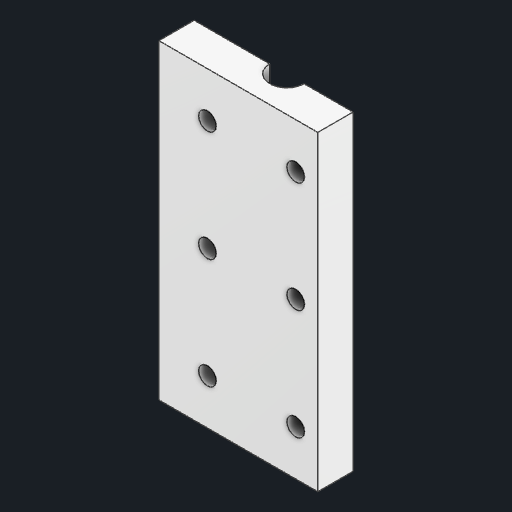
# Autodesk Inventor part: stand L_v3
Saved by Autodesk Inventor 2026.3 (Build 303398000, 398)
## iProperties
Created: 2026-09-14
Part Number: stand L_v3
Material: PBT 플라스틱
Document SubType Name: Modeling
Designer: khw
Density: 1.31 g/cm^3
Appearance: 매끄러움 - 흰색
Author: khw
Autodesk Inventor part; units mm, degrees
ref_plane "YZ Plane" through (0, 0, 0) normal (1, 0, 0) x (0, 1, 0)
ref_plane "XZ Plane" through (0, 0, 0) normal (0, 1, 0) x (-1, 0, 0)
sketch "스케치1" plane through (0, 0, 0) normal (1, 0, 0) x (0, 1, 0)
  circle A0 centre (0, 0) radius 12.5
  line L0 (-15.5, 15.5) -> (15.5, 15.5) construction
  line L1 (15.5, 15.5) -> (15.5, -15.5) construction
  line L2 (15.5, -15.5) -> (-15.5, -15.5) construction
  line L3 (-15.5, -15.5) -> (-15.5, 15.5) construction
  line L4 (-15.5, 15.5) -> (15.5, -15.5) construction
  line L5 (15.5, 15.5) -> (-15.5, -15.5) construction
  circle A1 centre (15.5, 15.5) radius 2
  circle A2 centre (15.5, -15.5) radius 2
  circle A3 centre (-15.5, -15.5) radius 2
  circle A4 centre (-15.5, 15.5) radius 2
  line L6 (0, 59) -> (0, -59) construction
  circle A5 centre (0, 59) radius 4.1
  circle A6 centre (0, -59) radius 4.1
  line L7 (0, 0) -> (-40, 0) construction
  arc A7 (-23.5, 0) -> (-40, 46.5) centre (-97.2727, 0) ccw
  line L8 (-40, 46.5) -> (-40, 79)
  line L9 (-40, 79) -> (30.5, 79)
  line L10 (30.5, 79) -> (30.5, -0.2641)
  circle A8 centre (0, 59) radius 12.5
  line L11 (-22, -22) -> (22, -22)
  line L12 (22, -22) -> (22, 22)
  line L13 (22, 22) -> (-12.9799, 22)
  line L14 (-22, 22) -> (-22, -22)
  line L15 (-22, -22) -> (22, 22) construction
  line L16 (22, -22) -> (-22, 22) construction
  arc A9 (-22.7897, 30.0588) -> (-30, 46.5) centre (-63.5156, 22) ccw
  line L17 (0, 46.5) -> (-30, 46.5)
  line L18 (0, 46.5) -> (5, 46.5)
  line L19 (5, 46.5) -> (12, 46.5)
  line L20 (22, 36.5) -> (22, 22)
  arc A10 (-22.7897, 30.0588) -> (-12.9799, 22) centre (-12.9799, 32) ccw
  line L21 (5, 22) -> (5, 46.5)
  line L22 (-5, 22) -> (-5, 46.5)
  arc A11 (22, 36.5) -> (12, 46.5) centre (12, 36.5) ccw
  line L23 (0, -59) -> (0, 59) construction
  circle A12 centre (0, -59) radius 4.1
  arc A13 (-40, -46.5) -> (-23.5, 0) centre (-97.2727, 0) ccw
  line L24 (-40, -46.5) -> (-40, -79)
  line L25 (-40, -79) -> (30.5, -79)
  line L26 (30.5, -79) -> (30.5, 0.2641)
  circle A14 centre (0, -59) radius 12.5
  line L27 (22, -22) -> (-12.9799, -22)
  arc A15 (-30, -46.5) -> (-22.7897, -30.0588) centre (-63.5156, -22) ccw
  line L28 (0, -46.5) -> (-30, -46.5)
  line L29 (0, -46.5) -> (5, -46.5)
  line L30 (5, -46.5) -> (12, -46.5)
  line L31 (22, -36.5) -> (22, -22)
  arc A16 (-12.9799, -22) -> (-22.7897, -30.0588) centre (-12.9799, -32) ccw
  line L32 (5, -22) -> (5, -46.5)
  line L33 (-5, -22) -> (-5, -46.5)
  arc A17 (12, -46.5) -> (22, -36.5) centre (12, -36.5) ccw
  point P0 (30.5, -0.2641)
  point P1 (-12.9799, -22)
  dimension "d16" = 25
  dimension "d0" = 25
  dimension "d1" = 31
  dimension "d2" = 31
  dimension "d3" = 4
  dimension "d4" = 4
  dimension "d5" = 4
  dimension "d6" = 4
  dimension "d7" = 118
  dimension "d8" = 8.2
  dimension "d9" = 8.2
  dimension "d10" = 40
  dimension "d11" = 15
  dimension "d12" = 8
  dimension "d13" = 20
  dimension "d14" = 40
  dimension "d17" = 44
  dimension "d18" = 44
  dimension "d19" = 10
  dimension "d20" = 10
  dimension "d21" = 10
  dimension "d22" = 10
  constraints: 68 end point, 23 symmetric about line, 17 point on circle, 16 centre point, 10 coincident, 8 point on line, 6 horizontal, 6 perpendicular, 5 midpoint, 5 tangent, 4 parallel, 2 vertical, 2 vertical alignment, 1 horizontal alignment, 1 line through centre, 9 other
  measures "d0" diameter of A0
  measures "d1" distance of L1.end L2.end
  measures "d2" distance of L0.end L1.end
  measures "d3" diameter of A1
  measures "d4" diameter of A2
  measures "d5" diameter of A3
  measures "d6" diameter of A4
  measures "d7" distance of L6.start L6.end
  measures "d8" diameter of A5
  measures "d9" diameter of A6
  measures "d10" distance of L7.start L7.end
  measures "d11" distance between parallel lines of L10 L1
  measures "d12" distance from line of L3 A7.start
  measures "d13" distance from line of L9 L6.start
  measures "d14" distance from line of L8 L6.start
  measures "d17" distance of L14.start L12.end
  measures "d18" distance of L12.end L11.end
  measures "d19" distance of L8.start L17.end
  measures "d20" radius of A10
  measures "d21" distance between parallel lines of L22 L21
  measures "d22" radius of A11
extrude "돌출1" add sketch "스케치1" along normal blind 6 contours A7 L8 L9 L10 L26 L25 L24 A13 | A8 | L18 L21 L13 L22 L17 | A14 | L11 L32 L29 L28 L33
sketch "스케치2" plane through (0, 30.5, 79) normal (0, 1, 0) x (1, 0, 0)
  line L0 (6, 0) -> (6, 32.5) projected
  line L1 (6, 0) -> (36, 0)
  line L2 (36, 0) -> (36, 8)
  line L3 (36, 8) -> (6, 8)
  line L4 (6, 8) -> (6, 0)
  circle A0 centre (21, 0) radius 3.9
  arc A1 (27, 8) -> (15, 8) centre (21, 0) ccw
  line L5 (21, 10) -> (6, 10)
  line L6 (36, 0) -> (0, 0)
  line L7 (0, 0) -> (0, -8)
  line L8 (0, -8) -> (36, -8)
  line L9 (36, -8) -> (36, 0)
  line L10 (0, 158) -> (0, 0) projected
  point P0 (0, 79)
  point P1 (6, 0)
  dimension "d25" = 30
  dimension "d26" = 8
  dimension "d27" = 7.8
  dimension "d28" = 20
  dimension "d29" = 8
  constraints: 18 end point, 4 parallel, 3 horizontal, 3 point on circle, 3 point on line, 2 centre point, 2 perpendicular, 1 coincident, 1 collinear, 1 midpoint, 1 tangent
  measures "d25" distance of L3.end L2.end
  measures "d26" distance of L2.end L1.end
  measures "d27" diameter of A0
  measures "d28" diameter of A1
  measures "d29" distance between parallel lines of L8 L1
extrude "돌출2" add sketch "스케치2" against normal up to surface (70.5 mm away) contours L0 L3 L2 L1 A0 | L1 A0 L9 L8 L7 L6 | L0 L5 A1 L3 | A1 L3
sketch "스케치3" plane through (0, -40, 46.5) normal (0, -1, 0) x (1, 0, 0)
  line L0 (36, 24.5) -> (27, 24.5) projected
  line L1 (6, 0) -> (6, -93) projected
  line L2 (36, 24.5) -> (6, 0)
  circle A0 centre (21, 32.5) radius 3.9 projected
  line L3 (0, 40.5) -> (0, 0) projected
  line L4 (0, 0) -> (6, 0) projected
  line L5 (6, 22.5) -> (6, 0) projected
  line L6 (21, 22.5) -> (6, 22.5) projected
  arc A1 (21, 22.5) -> (27, 24.5) centre (21, 32.5) ccw projected
  line L7 (36, 24.5) -> (27, 24.5) projected
  line L8 (36, 40.5) -> (36, 24.5) projected
  line L9 (0, 40.5) -> (36, 40.5) projected
  point P0 (0, -46.5)
  point P1 (27, 24.5)
  constraints: 2 end point
extrude "돌출3" add sketch "스케치3" against normal blind 8 contours L2 L5 L6 A1 L0
fillet "모깎기1" radius 4 5 edges at (6, -32, 57.75) (6, -0.75, 69) (24.1623, -32, 69.5132) (13.5, -32, 69) (31.5, -32, 71)
ref_plane "작업 평면1" through (36, 30.5, 79) normal (0, 0, -1) x (-1, 0, 0)
sketch "스케치4" plane through (36, 30.5, 79) normal (0, 0, -1) x (-1, 0, 0)
  line L0 (11.1, -70.5) -> (18.9, -70.5) construction
  line L1 (11.1, 0) -> (18.9, 0) construction
  line L2 (5, -10.25) -> (25, -10.25) construction
  line L3 (25, -10.25) -> (25, -60.25) construction
  line L4 (25, -60.25) -> (5, -60.25) construction
  line L5 (5, -60.25) -> (5, -10.25) construction
  line L6 (5, -10.25) -> (25, -60.25) construction
  line L7 (25, -10.25) -> (5, -60.25) construction
  line L8 (15, 0) -> (15, -70.5) construction
  line L9 (25, -35.25) -> (5, -35.25) construction
  circle A0 centre (25, -10.25) radius 2
  circle A1 centre (25, -35.25) radius 2
  circle A2 centre (25, -60.25) radius 2
  circle A3 centre (5, -60.25) radius 2
  circle A4 centre (5, -35.25) radius 2
  circle A5 centre (5, -10.25) radius 2
  point P0 (36, -30.5)
  point P1 (15, -35.25)
  dimension "d35" = 20
  dimension "d36" = 50
  dimension "d37" = 4
  dimension "d38" = 4
  dimension "d39" = 4
  dimension "d40" = 4
  dimension "d41" = 4
  dimension "d42" = 4
  constraints: 16 end point, 7 midpoint, 6 centre point, 6 coincident, 2 parallel, 1 horizontal, 1 perpendicular
  measures "d35" distance of L3.end L4.end
  measures "d36" distance of L2.end L3.end
  measures "d37" diameter of A0
  measures "d38" diameter of A1
  measures "d39" diameter of A2
  measures "d40" diameter of A3
  measures "d41" diameter of A4
  measures "d42" diameter of A5
extrude "돌출4" cut sketch "스케치4" along normal through all both and the other way through all
mirror "미러2" about plane through (0, 0, 0) normal (0, 0, 1) of "모깎기1", "돌출3", "돌출2", "돌출4"
split "분할1" plane through (36, 30.5, 79) removes the side toward (0, 0, -1)
ref_plane "작업 평면3" through (36, 30.5, -79) normal (0, 0, -1) x (-1, 0, 0)
